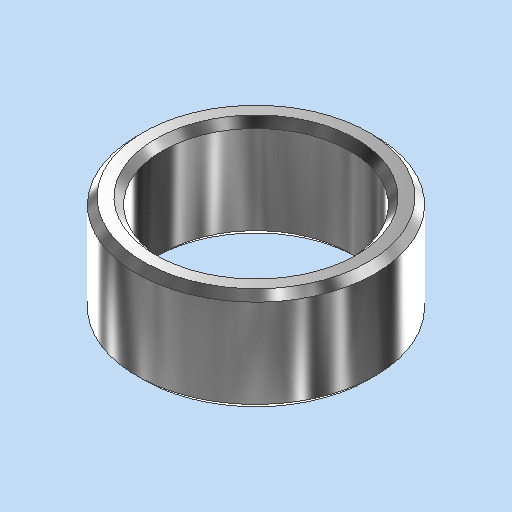
# Autodesk Inventor part: R412000668_070216_001
Saved by Autodesk Inventor 2023.3 (Build 273359000, 359)
## iProperties
Company: Robert BOSCH GmbH
Created: 2006-08-29
Part Number: R412000668_070216_001
Description: =<RBPARTNOTITLE2>
Vendor: Bosch Rexroth
Document SubType Name: Modeling
User Status: Freigegeben
Designer: GMA9BA
Density: 1 g/cm^3
Material: Allgemein
Appearance: Schwarzchrom
GAIN_REFID: 20__r412000668_070216_001:D3091
RBGBPRODUCERTYPETERM: R412000668
RBGBPRODUCERNAME: Bosch
RBPARTNOTITLE2: Zentrierhülse D=7mm
RBDRAWINGOUTPUTNO: 00
RBPARTMADEOF: R039660543
RBDRAWINGSHEET: 000
DEF_STKID: N6262
RBDRAWINGMISSINGSPEC: --
AnP_Kategorie: 22
Subject: Zentrierhülse D=7mm
Author: GMA9BA
Keywords: =<RBPARTMADEOF>
Comments: =<RBSURFACE2>
Revision Number: 01
Autodesk Inventor part; units mm, degrees
ref_plane "YZ Plane" through (0, 0, 0) normal (1, 0, 0) x (0, 1, 0)
ref_plane "XZ Plane" through (0, 0, 0) normal (0, 1, 0) x (-1, 0, 0)
ref_plane "XY Plane" through (0, 0, 0) normal (0, 0, 1) x (1, 0, 0)
sketch "Skizze1" plane through (0, 0, 0) normal (0, 0, 1) x (1, 0, 0)
  circle A0 centre (0, 0) radius 3.5
  circle A1 centre (0, 0) radius 2.75
  dimension "d0" = 7
  dimension "d1" = 5.5
  constraints: 2 centre point, 2 coincident
  measures "d0" diameter of A0
  measures "d1" diameter of A1
extrude "Extrusion1" add sketch "Skizze1" along normal blind 3
chamfer "Fase1" distance 0.2 angle 45 4 edges at (-3.5, 0, 3) (-2.75, 0, 3) (-3.5, 0, 0) (-2.75, 0, 0)
